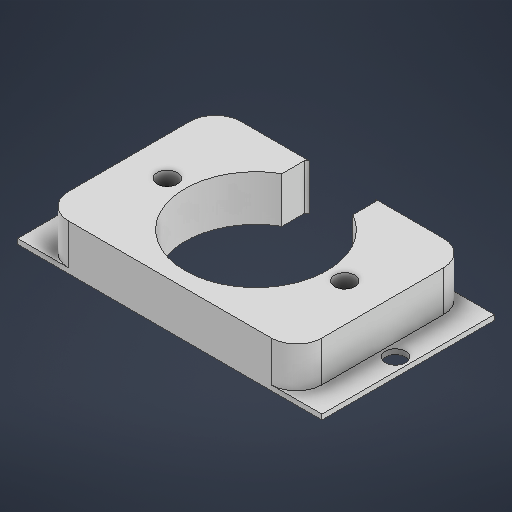
# Autodesk Inventor part: azimuth_drive
Saved by Autodesk Inventor 2027.1 (Build 311270010, 270A)
## iProperties
Created: 2026-11-08
Part Number: azimuth_drive
Material: Ogólny
Document SubType Name: Modeling
Designer: User
Density: 1 g/cm^3
Appearance: Domyślna
Author: User
Autodesk Inventor part; units mm, degrees
ref_plane "YZ Plane" through (0, 0, 0) normal (1, 0, 0) x (0, 1, 0)
ref_plane "XZ Plane" through (0, 0, 0) normal (0, 1, 0) x (-1, 0, 0)
ref_plane "XY Plane" through (0, 0, 0) normal (0, 0, 1) x (1, 0, 0)
sketch "Szkic1" plane through (0, 0, 0) normal (0, 1, 0) x (-1, 0, 0)
  line L0 (-7, -12.1244) -> (-7, -16.5)
  arc A0 (-7, -16.5) -> (-6.5, -17) centre (-6.5, -16.5) ccw
  line L1 (-6.5, -17) -> (6.5, -17)
  arc A1 (6.5, -17) -> (7, -16.5) centre (6.5, -16.5) ccw
  line L2 (7, -16.5) -> (7, -12.1244)
  arc A2 (7, -12.1244) -> (13.5554, -3.5) centre (0, 0) ccw
  line L3 (13.5554, -3.5) -> (17.5, -3.5)
  arc A3 (17.5, -3.5) -> (17.5, 3.5) centre (17.5, 0) ccw
  line L4 (17.5, 3.5) -> (13.5554, 3.5)
  arc A4 (13.5554, 3.5) -> (-13.5554, 3.5) centre (0, 0) ccw
  line L5 (-13.5554, 3.5) -> (-17.5, 3.5)
  arc A5 (-17.5, 3.5) -> (-17.5, -3.5) centre (-17.5, 0) ccw
  line L6 (-17.5, -3.5) -> (-13.5554, -3.5)
  arc A6 (-13.5554, -3.5) -> (-7, -12.1244) centre (0, 0) ccw
  circle A7 centre (0, 7) radius 4.5
  circle A8 centre (17.5, 0) radius 2
  circle A9 centre (-17.5, 0) radius 2
  line L7 (-2, 8.5) -> (2, 8.5)
  arc A10 (-2, 8.5) -> (-2, 5.5) centre (0, 7) ccw
  line L8 (2, 5.5) -> (-2, 5.5)
  arc A11 (2, 5.5) -> (2, 8.5) centre (0, 7) ccw
  line L9 (-2, 8.5) -> (2, 8.5)
  arc A12 (2, 8.5) -> (-2, 8.5) centre (0, 7) ccw
  line L10 (2, 8.5) -> (-2, 8.5)
  arc A13 (-2, 5.5) -> (2, 5.5) centre (0, 7) ccw
  line L11 (-2, 5.5) -> (2, 5.5)
  line L12 (-25, 17) -> (25, 17)
  line L13 (25, 17) -> (25, -17)
  line L14 (25, -17) -> (-25, -17)
  line L15 (-25, -17) -> (-25, 17)
  line L16 (-25, 17) -> (25, -17) construction
  line L17 (25, 17) -> (-25, -17) construction
  circle A14 centre (0, 0) radius 14
  point P0 (0, 0)
  point P1 (0, 0)
  point P2 (13.5554, -3.5)
  point P3 (-13.5554, 3.5)
  dimension "d0" = 50
  dimension "d1" = 34
  constraints: 36 end point, 22 point on circle, 14 centre point, 2 midpoint, 2 parallel, 1 coincident, 1 horizontal, 1 perpendicular, 3 other
  measures "d0" distance of L13.end L14.end
  measures "d1" distance of L12.end L13.end
extrude "Wyciągnięcie proste1" add sketch "Szkic1" along normal blind 8 contours L0 A0 L14 L15 L12 L13 A1 L2 A2 L3 A3 L4 A4 L5 A5 L6 A6 | L6 A5 L5 A14 | A14 L4 A3 L3
fillet "Zaokrąglenie1" radius 5 4 edges at (25, 4, 17) (-25, 4, 17) (-25, 4, -17) (25, 4, -17)
sketch "Szkic2" plane through (0, 0, 0) normal (0, -1, 0) x (1, 0, 0)
  circle A0 centre (-17.5, 0) radius 2 projected
  circle A1 centre (-17.5, 0) radius 2.7
  circle A2 centre (17.5, 0) radius 2 projected
  circle A3 centre (17.5, 0) radius 2.7
  point P0 (0, 0)
  dimension "d5" = 5.4
  dimension "d6" = 5.4
  constraints: 2 centre point, 2 coincident
  measures "d5" diameter of A1
  measures "d6" diameter of A3
extrude "Wyciągnięcie proste2" cut sketch "Szkic2" against normal blind 5
sketch "Szkic3" plane through (0, 0, 0) normal (0, -1, 0) x (1, 0, 0)
  line L0 (30, -17) -> (-30, -17)
  line L1 (-30, -17) -> (-30, 17)
  line L2 (-30, 17) -> (30, 17)
  line L3 (30, 17) -> (30, -17)
  line L4 (30, -17) -> (-30, 17) construction
  line L5 (-30, -17) -> (30, 17) construction
  line L6 (0, 0) -> (0, 17) construction
  line L7 (0, 0) -> (-30, 0) construction
  line L8 (-30, 0) -> (-25, 0) construction
  line L9 (-25, -12) -> (-25, 12) projected
  circle A0 centre (-27.5, 0) radius 2
  circle A1 centre (27.5, 0) radius 2
  circle A2 centre (-17.5, 0) radius 2.7 projected
  circle A3 centre (17.5, 0) radius 2.7 projected
  arc A4 (20, -17) -> (25, -12) centre (20, -12) ccw projected
  line L10 (25, 12) -> (25, -12) projected
  arc A5 (25, 12) -> (20, 17) centre (20, 12) ccw projected
  line L11 (-20, 17) -> (20, 17) projected
  arc A6 (-20, 17) -> (-25, 12) centre (-20, 12) ccw projected
  line L12 (-25, -12) -> (-25, 12) projected
  arc A7 (-25, -12) -> (-20, -17) centre (-20, -12) ccw projected
  line L13 (-6.5, -17) -> (-20, -17) projected
  arc A8 (-7, -16.5) -> (-6.5, -17) centre (-6.5, -16.5) ccw projected
  line L14 (-7, -12.1244) -> (-7, -16.5) projected
  arc A9 (7, -12.1244) -> (-7, -12.1244) centre (0, 0) ccw projected
  line L15 (7, -16.5) -> (7, -12.1244) projected
  arc A10 (6.5, -17) -> (7, -16.5) centre (6.5, -16.5) ccw projected
  line L16 (20, -17) -> (6.5, -17) projected
  dimension "d9" = 60
  dimension "d10" = 34
  dimension "d11" = 4
  constraints: 18 end point, 6 midpoint, 2 centre point, 2 parallel, 1 horizontal, 1 perpendicular, 1 symmetric about line, 1 other
  measures "d9" distance of L1.end L2.end
  measures "d10" distance of L0.end L1.end
  measures "d11" diameter of A0
extrude "Wyciągnięcie proste3" add sketch "Szkic3" along normal blind 1 contours L0 A4 L10 A5 L2 L3 | L0 A10 L15 A9 L14 A8 A7 L9 A6 L2 A5 L10 A4 | A6 L9 A7 L0 L1 L2
